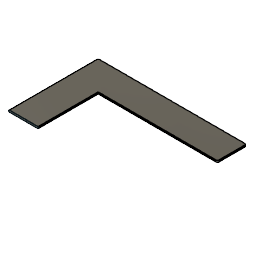
Front Counter - Top (Autodesk Fusion 360 design; units mm, degrees)
Autodesk Fusion 360 part; units mm, degrees
sketch "Sketch1" plane through (0, 0, 0) normal (0, 0, 1) x (1, 0, 0)
  line L0 (0, 0) -> (0, 180)
  line L1 (0, 0) -> (60, 0)
  line L2 (60, 0) -> (60, 120)
  line L3 (60, 120) -> (300, 120)
  line L4 (0, 180) -> (300, 180)
  line L5 (300, 180) -> (300, 120)
  dimension "d1" = 180
  dimension "d2" = 60
  dimension "d3" = 120
  dimension "d4" = 240
  constraint coincident L0.start L1.start
  constraint vertical L0
  constraint perpendicular L0 L1
  constraint perpendicular L1 L2
  constraint perpendicular L2 L3
  constraint perpendicular L0 L4
  constraint perpendicular L3 L5
  measures "d1" distance of L0.start L0.end
  measures "d2" distance of L0.start L1.end
  measures "d3" distance of L1.end L2.end
  measures "d4" distance of L2.end L3.end
extrude "Extrude1" add sketch "Sketch1" along normal blind 3.5
chamfer "Chamfer1" distance 4 angle 45 1 edges at (0, 180, 1.75)
chamfer "Chamfer2" distance 4 angle 45 1 edges at (300, 120, 1.75)
chamfer "Chamfer3" distance 4 angle 45 1 edges at (300, 180, 1.75)
fillet "Fillet1" radius 1 1 edges at (178, 120, 3.5)
fillet "Fillet2" radius 1 1 edges at (178, 120, 0)
fillet "Fillet3" radius 1 1 edges at (300, 150, 0)
fillet "Fillet4" radius 1 1 edges at (300, 150, 3.5)
fillet "Fillet5" radius 1 1 edges at (150, 180, 3.5)
fillet "Fillet6" radius 1 1 edges at (150, 180, 0)
fillet "Fillet7" radius 1 1 edges at (0, 88, 0)
fillet "Fillet8" radius 1 1 edges at (0, 88, 3.5)
fillet "Fillet9" radius 1 1 edges at (60, 60.5, 0)
fillet "Fillet10" radius 1 1 edges at (60, 60.5, 3.5)
sketch "Sketch2" plane through (0, 0, 0) normal (0, -1, 0) x (1, 0, 0)
  arc A0 (60, 2.5) -> (59, 3.5) centre (59, 2.5) ccw
  line L0 (59, 3.5) -> (1, 3.5)
  arc A1 (1, 3.5) -> (0, 2.5) centre (1, 2.5) ccw
  line L1 (0, 2.5) -> (0, 1)
  arc A2 (0, 1) -> (1, 0) centre (1, 1) ccw
  line L2 (1, 0) -> (59, 0)
  arc A3 (59, 0) -> (60, 1) centre (59, 1) ccw
  line L3 (60, 1) -> (60, 2.5)
